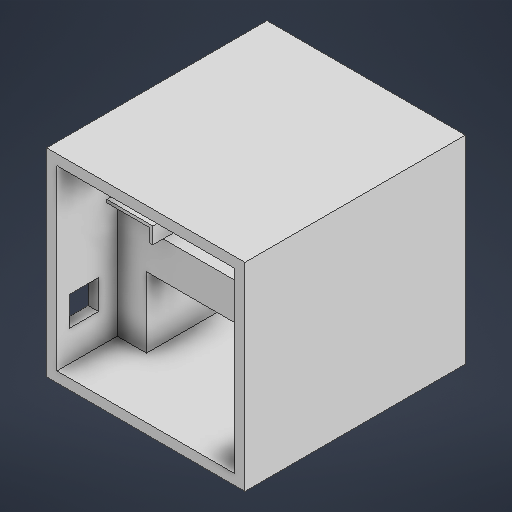
# Autodesk Inventor part: nowypojemnik
Saved by Autodesk Inventor 2026.1 (Build 301233020, 233B)
## iProperties
Created: 2026-09-20
Part Number: nowypojemnik
Material: Ogólny
Document SubType Name: Modeling
Designer: Bronh
Density: 1 g/cm^3
Appearance: Domyślna
Author: Bronh
Autodesk Inventor part; units mm, degrees
ref_plane "YZ Plane" through (0, 0, 0) normal (1, 0, 0) x (0, 1, 0)
ref_plane "XZ Plane" through (0, 0, 0) normal (0, 1, 0) x (-1, 0, 0)
ref_plane "XY Plane" through (0, 0, 0) normal (0, 0, 1) x (1, 0, 0)
sketch "Szkic1" plane through (0, 0, 0) normal (0, 1, 0) x (-1, 0, 0)
  line L0 (67.5, 75) -> (-67.5, 75)
  line L1 (-67.5, 75) -> (-67.5, -75)
  line L2 (-67.5, -75) -> (67.5, -75)
  line L3 (67.5, -75) -> (67.5, 75)
  line L4 (67.5, 75) -> (-67.5, -75) construction
  line L5 (-67.5, 75) -> (67.5, -75) construction
  point P0 (0, 0)
  dimension "d1" = 150
  dimension "d0" = 135
  constraints: 12 end point, 2 midpoint, 2 parallel, 1 horizontal, 1 perpendicular
  measures "d1" distance of L0.end L1.end
  measures "d0" distance of L1.end L2.end
extrude "Wyciągnięcie proste1" add sketch "Szkic1" along normal blind 135
shell "Skorupa1" thickness 7 removed faces 1 at (-22.5, 45, 75)
sketch "Szkic2" plane through (-60.5, 7, -68) normal (0, 0, 1) x (1, 0, 0)
  line L0 (0, 0) -> (0, 121) projected
  line L1 (0, 73) -> (95, 73)
  line L2 (95, 73) -> (95, 48)
  line L3 (95, 48) -> (0, 48)
  line L4 (0, 48) -> (0, 73)
  line L5 (121, 121) -> (121, 0) projected
  line L6 (0, 121) -> (121, 121) projected
  point P0 (60.5, -7)
  point P1 (0, 48)
  dimension "d6" = 25
  dimension "d7" = 26
  dimension "d8" = 48
  constraints: 8 end point, 2 parallel, 1 horizontal, 1 perpendicular, 1 point on line
  measures "d6" distance of L1.end L2.end
  measures "d7" distance between parallel lines of L5 L2
  measures "d8" distance between parallel lines of L6 L1
extrude "Wyciągnięcie proste2" add sketch "Szkic2" along normal blind 102
sketch "Szkic3" plane through (-60.5, 7, -68) normal (0, 0, 1) x (1, 0, 0)
  line L0 (0, 48) -> (0, 73) projected
  line L1 (121, 0) -> (0, 0) projected
  line L2 (0, 48) -> (20, 48)
  line L3 (20, 48) -> (20, 0)
  line L4 (20, 0) -> (0, 0)
  line L5 (0, 0) -> (0, 48)
  point P0 (60.5, -7)
  dimension "d13" = 20
  constraints: 8 end point, 2 parallel, 1 horizontal, 1 perpendicular, 1 point on line
  measures "d13" distance between parallel lines of L5 L3
extrude "Wyciągnięcie proste3" add sketch "Szkic3" along normal blind 102
sketch "Szkic4" plane through (-67.5, 0, -75) normal (-1, 0, 0) x (0, 0, 1)
  line L0 (141.6954, 47.8748) -> (121.6954, 47.8748)
  line L1 (121.6954, 47.8748) -> (121.6954, 27.8748)
  line L2 (121.6954, 27.8748) -> (141.6954, 27.8748)
  line L3 (141.6954, 27.8748) -> (141.6954, 47.8748)
  point P0 (75, 0)
  dimension "d14" = 20
  dimension "d15" = 20
  constraints: 8 end point, 2 parallel, 1 horizontal, 1 perpendicular
  measures "d14" distance of L2.end L1.end
  measures "d15" distance of L1.end L0.end
extrude "Wyciągnięcie proste4" cut sketch "Szkic4" against normal blind 7
sketch "Szkic5" plane through (-60.5, 128, -68) normal (0, 0, 1) x (1, 0, 0)
  line L0 (0, -121) -> (0, 0) projected
  line L1 (0, -48) -> (95, -48) projected
  line L2 (0, -36.8963) -> (31.3057, -36.8963)
  line L3 (31.3057, -36.8963) -> (31.3057, -48)
  line L4 (31.3057, -48) -> (0, -48)
  line L5 (0, -48) -> (0, -36.8963)
  point P0 (60.5, -128)
  constraints: 8 end point, 2 parallel, 2 point on line, 1 horizontal, 1 perpendicular
extrude "Wyciągnięcie proste5" add sketch "Szkic5" along normal blind 102
sketch "Szkic6" plane through (-60.5, 7, 34) normal (0, 0, 1) x (1, 0, 0)
  line L0 (0, 0) -> (0, 84.1037) projected
  line L1 (31.3057, 73) -> (31.3057, 84.1037) projected
  line L2 (0, 84.1037) -> (31.3057, 84.1037)
  line L3 (31.3057, 84.1037) -> (31.3057, 82.0605)
  line L4 (31.3057, 82.0605) -> (0, 82.0605)
  line L5 (0, 82.0605) -> (0, 84.1037)
  line L6 (29.0294, 82.0605) -> (31.3057, 82.0605)
  line L7 (31.3057, 82.0605) -> (31.3057, 73)
  line L8 (31.3057, 73) -> (29.0294, 73)
  line L9 (29.0294, 73) -> (29.0294, 82.0605)
  point P0 (60.5, -7)
  constraints: 16 end point, 4 parallel, 2 horizontal, 2 perpendicular, 2 point on line
extrude "Wyciągnięcie proste6" add sketch "Szkic6" along normal blind 7
